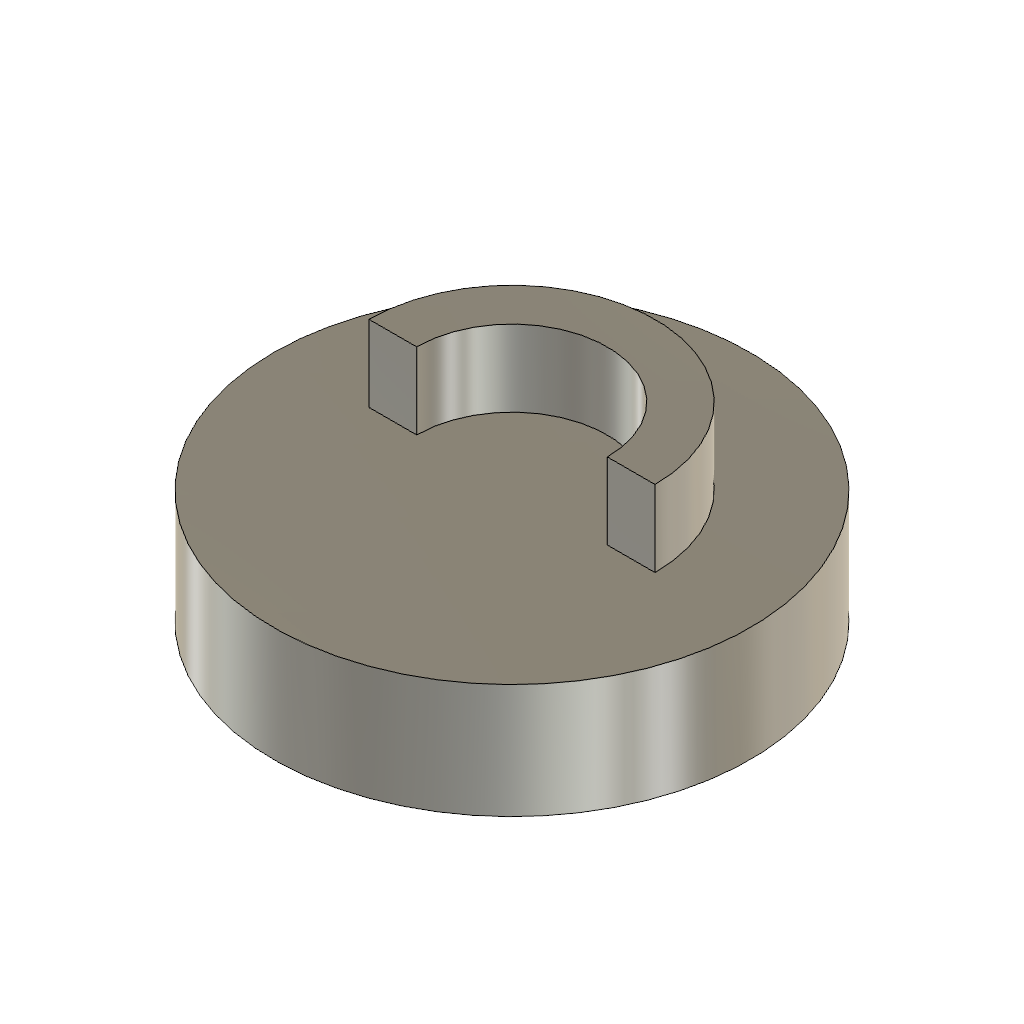
vendor_RevolveJoin (Autodesk Fusion 360 design; units mm, degrees)
Autodesk Fusion 360 part; units mm, degrees
sketch "Disc sketch" plane through (0, 0, 0) normal (0, 0, 1) x (1, 0, 0)
  circle A0 centre (0, 0) radius 25
extrude "Disc extrude" add sketch "Disc sketch" along normal blind 12
sketch "Ring sketch" plane through (0, 0, 0) normal (0, 1, 0) x (1, 0, 0)
  line L0 (10, -10) -> (15, -10)
  line L1 (15, -10) -> (15, -20)
  line L2 (15, -20) -> (10, -20)
  line L3 (10, -20) -> (10, -10)
revolve "Ring revolve" add sketch "Ring sketch" angle 180 about axis through (0, 0, 0) along (0, 0, 1)
equation "height = 20.0 mm"
